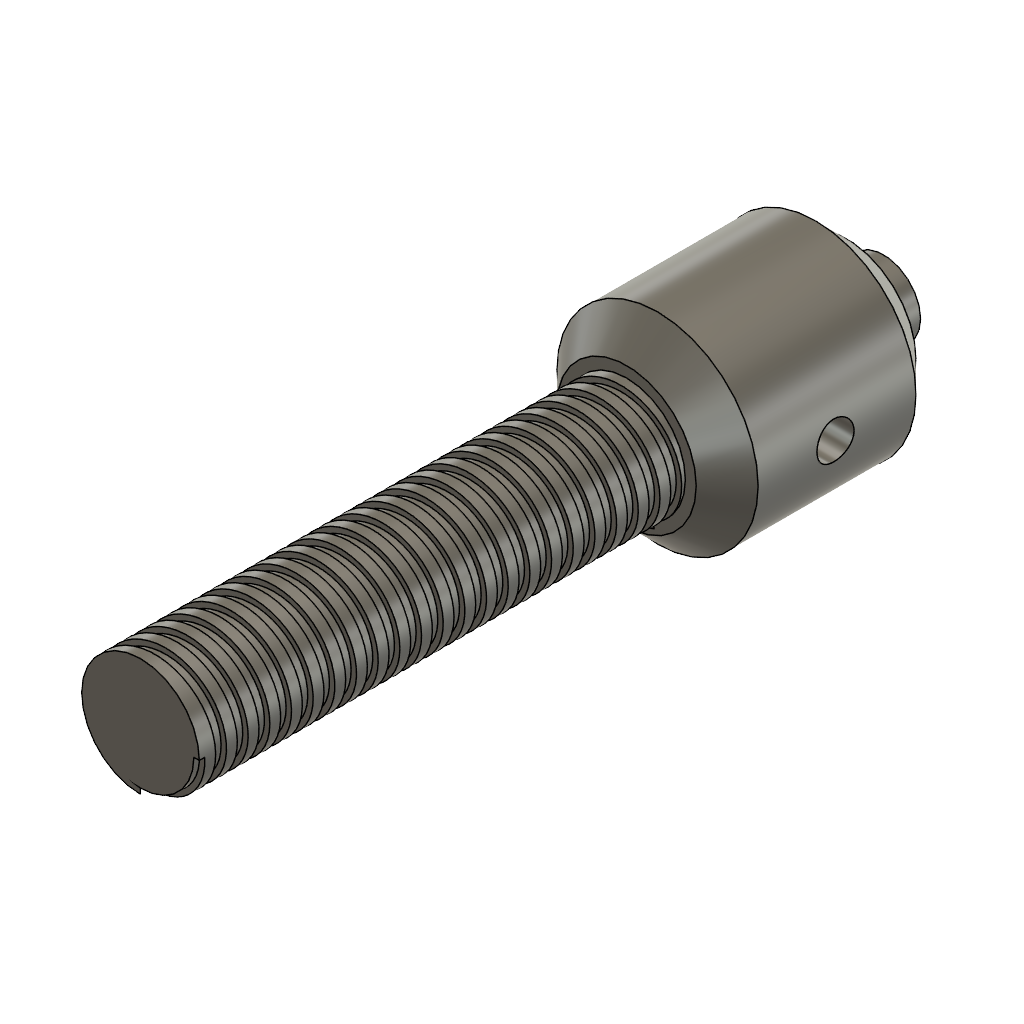
Screw spindle (Autodesk Fusion 360 design; units mm, degrees)
part number: 2026-11-04-17-31-29-919
Autodesk Fusion 360 part; units mm, degrees
sketch "Sketch1" plane through (0, 0, 0) normal (0, 0, 1) x (1, 0, 0)
  circle A0 centre (0, 0) radius 32.5
  dimension "d1" = 65
  constraint coincident A0.centre origin
  measures "d1" diameter of A0
extrude "Extrude1" add sketch "Sketch1" against normal blind 71
chamfer "Chamfer1" distance 10 angle 45 1 edges at (-30.3006, -11.7525, 0) measured on face at (-1.1612, 8.4698, 0) tangent chain off
chamfer "Chamfer2" distance 10 angle 45 1 edges at (-30.3006, 11.7525, -71) measured on face at (-1.1612, 8.4698, -71) tangent chain off
sketch "Sketch2" plane through (0, 0, 0) normal (0, 0, 1) x (1, 0, 0)
  circle A0 centre (0, 0) radius 22.5
  circle A1 centre (0, 0) radius 19
  dimension "d8" = 38
  constraint coincident A0.centre A1.centre
  measures "d8" diameter of A1
extrude "Extrude2" add sketch "Sketch2" along normal blind 157 contours A1
coil "CoilPrimitive1" cut diameter 38 section square size 3.5 on centre turns 22.42857 pitch 7 right hand placed x (1, 0, 0) y (0, -1, 0) z (0, 0, -1) at (0, 0, 157)
ref_plane "WorkPlane1" through (1.0243, 10.5617, -71) normal (-1, 0, 0) x (0, 0, -1)
sketch "Sketch4" plane through (1.0243, 0, 0) normal (-1, 0, 0) x (0, 0, 1)
  line L0 (-71, -22.5) -> (-71, 22.5)
  line L1 (0, 22.5) -> (0, -22.5)
  circle A0 centre (-35, 0) radius 6
  dimension "d18" = 12
  dimension "d19" = 35
  measures "d18" diameter of A0
  measures "d19" distance of origin A0.centre
extrude "Extrude3" cut sketch "Sketch4" along normal mid plane 65
sketch "Sketch5" plane through (0, 0, -71) normal (0, 0, -1) x (-1, 0, 0)
  circle A0 centre (0, 0) radius 22.5
  circle A1 centre (0, 0) radius 12
  dimension "d22" = 24
  constraint coincident A0.centre A1.centre
  measures "d22" diameter of A1
extrude "Extrude4" add sketch "Sketch5" along normal blind 12 contours A1
sketch "Sketch6" plane through (0, 0, -83) normal (0, 0, -1) x (-1, 0, 0)
  circle A0 centre (0, 0) radius 12
  circle A1 centre (0, 0) radius 6
  dimension "d25" = 12
  constraint coincident A0.centre A1.centre
  measures "d25" diameter of A1
extrude "Extrude5" cut sketch "Sketch6" against normal blind 27 contours A1
thread "Thread3" "ISO Metric profile 12.0 M12x1.5 M12x1.5 6H" major diameter 12.203 minor diameter 10.526 pitch 1.5 angle 60 resizes the face on face at (-5.9925, -0.2991, -65)
